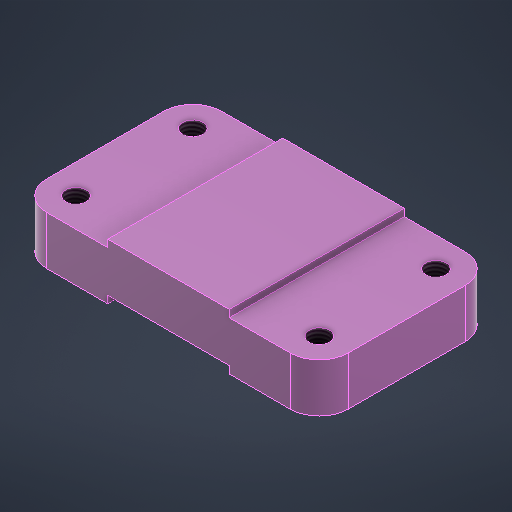
# Autodesk Inventor part: Base
Saved by Autodesk Inventor 2026.3 (Build 303398000, 398)
## iProperties
Created: 2026-11-02
Part Number: Base
Material: Iron, Gray
Document SubType Name: Modeling
Designer: ADMIN
Density: 7.15 g/cm^3
Appearance: Smooth - Purple
Author: ADMIN
Autodesk Inventor part; units mm, degrees
ref_plane "YZ Plane" through (0, 0, 0) normal (1, 0, 0) x (0, 1, 0)
ref_plane "XZ Plane" through (0, 0, 0) normal (0, 1, 0) x (-1, 0, 0)
ref_plane "XY Plane" through (0, 0, 0) normal (0, 0, 1) x (1, 0, 0)
sketch "Sketch1" plane through (0, 0, 0) normal (0, 0, 1) x (1, 0, 0)
  line L0 (-62, 0) -> (-62, 20)
  line L1 (-62, 20) -> (-25, 20)
  line L2 (-25, 20) -> (-25, 23)
  line L3 (-25, 23) -> (25, 23)
  line L4 (25, 23) -> (25, 20)
  line L5 (25, 20) -> (62, 20)
  line L6 (62, 20) -> (62, 0)
  line L7 (62, 0) -> (25, 0)
  line L8 (25, 0) -> (25, 3)
  line L9 (25, 3) -> (-25, 3)
  line L10 (-25, 3) -> (-25, 0)
  line L11 (-25, 0) -> (-62, 0)
  line L12 (0, 23) -> (0, 3)
  point P0 (0, 0)
  dimension "d4" = 124
  dimension "d5" = 50
  dimension "d6" = 3
  dimension "d7" = 3
  dimension "d8" = 20
  constraints: 26 end point, 8 perpendicular, 7 point on line, 6 symmetric about line, 2 midpoint, 1 horizontal alignment, 1 vertical, 1 vertical alignment
  measures "d4" distance between parallel lines of L6 L0
  measures "d5" distance between parallel lines of L8 L10
  measures "d6" distance of L1.end L2.end
  measures "d7" distance of L9.end L10.end
  measures "d8" distance of L0.start L0.end
extrude "Extrusion1" add sketch "Sketch1" along normal mid plane 72
fillet "Fillet1" radius 12 4 edges at (62, 10, 36) (62, 10, -36) (-62, 10, -36) (-62, 10, 36)
sketch "Sketch2" plane through (-25, 20, 36) normal (0, 1, 0) x (1, 0, 0)
  arc A0 (-25, 72) -> (-37, 60) centre (-25, 60) ccw projected
  arc A1 (87, 60) -> (75, 72) centre (75, 60) ccw projected
  arc A2 (75, 0) -> (87, 12) centre (75, 12) ccw projected
  arc A3 (-37, 12) -> (-25, 0) centre (-25, 12) ccw projected
  point P0 (25, 36)
  constraints: 4 coincident
hole "Hole1" at (-50, 20, -24) at (50, 20, -24) at (50, 20, 24) at (-50, 20, 24) direction (0, -1, 0) diameter 8.376 depth 15 tip angle 118 thread size "M10x1.5" class "6H" standard "ISO Metric profile"
body "Solid1"
